Autodesk Fusion 360 part; units mm, degrees
(part 12 of 18)
  line L9010 (123.304, -201.904) -> (123.641, -202.381)
  line L9011 (33.5654, -214.426) -> (34.0223, -214.047)
  line L9012 (54.0585, -215.371) -> (54.5813, -215.09)
  line L9013 (19.0291, -207.555) -> (19.0332, -207.131)
  line L9014 (37.1268, -207.35) -> (37.1251, -207.524)
  line L9015 (29.2581, -216.323) -> (28.6766, -216.38)
  line L9016 (55.5654, -214.426) -> (56.0223, -214.047)
  line L9017 (52.4039, -216.096) -> (51.8346, -216.228)
  line L9018 (41.7774, -210.959) -> (41.5618, -210.416)
  line L9019 (50.0926, -216.4) -> (49.5085, -216.382)
  line L9020 (19.3817, -209.86) -> (19.2379, -209.293)
  line L9021 (47.1318, -215.807) -> (47.6987, -215.983)
  line L9022 (35.9457, -202.88) -> (36.2178, -203.397)
  line L9023 (36.7582, -209.547) -> (36.8847, -208.967)
  line L9024 (55.5358, -214.568) -> (55.0587, -214.905)
  line L9025 (41.0332, -207.131) -> (41.0347, -206.971)
  line L9026 (124.957, -205.608) -> (125.051, -206.184)
  line L9027 (23.2676, -199.684) -> (23.7724, -199.389)
  line L9028 (58.3321, -203.88) -> (58.084, -203.34)
  line L9029 (36.084, -203.34) -> (35.8006, -202.818)
  line L9030 (20.402, -202.554) -> (20.7274, -202.069)
  line L9031 (110.32, -200.367) -> (110.783, -200.01)
  line L9032 (19.495, -204.792) -> (19.3443, -205.366)
  line L9033 (53.9179, -199.261) -> (53.3734, -199.024)
  line L9034 (26.5208, -198.435) -> (27.0994, -198.353)
  line L9035 (50.483, -198.404) -> (49.8893, -198.397)
  line L9036 (58.7185, -205.002) -> (58.5439, -204.435)
  line L9037 (43.3513, -213.406) -> (42.9746, -212.959)
  line L9038 (21.3513, -213.406) -> (20.9746, -212.959)
  line L9039 (36.5935, -210.117) -> (36.7582, -209.547)
  line L9040 (22.539, -214.387) -> (23.0175, -214.739)
  line L9041 (21.8816, -200.753) -> (22.3203, -200.367)
  line L9042 (24.2951, -199.128) -> (24.8336, -198.901)
  line L9043 (42.7955, -202.137) -> (42.466, -202.631)
  line L9044 (23.6204, -215.227) -> (23.1214, -214.923)
  line L9045 (19.078, -206.388) -> (19.1589, -205.81)
  line L9046 (19.3803, -209.486) -> (19.541, -210.058)
  line L9047 (21.9695, -200.801) -> (21.5489, -201.22)
  line L9048 (24.5778, -215.593) -> (25.1318, -215.807)
  line L9049 (118.005, -198.508) -> (118.571, -198.651)
  line L9050 (36.9575, -205.608) -> (37.0514, -206.184)
  line L9051 (24.9847, -198.946) -> (24.4345, -199.169)
  line L9052 (47.5484, -198.759) -> (46.9847, -198.946)
  line L9053 (108.108, -203.06) -> (108.402, -202.554)
  line L9054 (41.3443, -205.366) -> (41.2321, -205.949)
  line L9055 (25.7803, -216.104) -> (25.2202, -215.937)
  line L9056 (41.9741, -211.163) -> (42.2446, -211.691)
  line L9057 (54.5607, -215.211) -> (54.0441, -215.484)
  line L9058 (29.4301, -198.402) -> (30.0047, -198.508)
  line L9059 (41.5618, -210.416) -> (41.3817, -209.86)
  line L9060 (24.8336, -198.901) -> (25.3856, -198.709)
  line L9061 (20.2446, -211.691) -> (20.5495, -212.201)
  line L9062 (20.1085, -203.06) -> (20.402, -202.554)
  line L9063 (112.295, -199.128) -> (112.834, -198.901)
  line L9064 (57.8006, -202.818) -> (57.4833, -202.317)
  line L9065 (107.277, -205.237) -> (107.432, -204.674)
  line L9066 (22.3203, -200.367) -> (22.7829, -200.01)
  line L9067 (42.466, -202.631) -> (42.17, -203.146)
  line L9068 (44.539, -214.387) -> (45.0175, -214.739)
  line L9069 (34.3423, -200.952) -> (33.9045, -200.551)
  line L9070 (35.6409, -202.381) -> (35.9457, -202.88)
  line L9071 (58.8847, -208.967) -> (58.9725, -208.379)
  line L9072 (32.1995, -199.294) -> (32.7108, -199.576)
  line L9073 (52.9627, -215.827) -> (53.5182, -215.617)
  line L9074 (20.8876, -212.689) -> (21.2572, -213.154)
  line L9075 (43.2572, -213.154) -> (43.6569, -213.593)
  line L9076 (59.1251, -207.524) -> (59.0951, -208.107)
  line L9077 (33.2028, -199.892) -> (33.6734, -200.238)
  line L9078 (124.659, -204.478) -> (124.827, -205.038)
  line L9079 (21.7561, -213.827) -> (21.3513, -213.406)
  line L9080 (33.6734, -200.238) -> (34.1207, -200.614)
  line L9081 (27.4521, -216.283) -> (28.0455, -216.305)
  line L9082 (116.85, -198.333) -> (117.43, -198.402)
  line L9083 (30.8143, -198.824) -> (30.2432, -198.661)
  line L9084 (58.5439, -204.435) -> (58.3321, -203.88)
  line L9085 (49.4521, -216.283) -> (50.0455, -216.305)
  line L9086 (35.1986, -212.934) -> (34.8234, -213.382)
  line L9087 (36.7806, -209.829) -> (36.6024, -210.386)
  line L9088 (120.199, -199.294) -> (120.711, -199.576)
  line L9089 (41.3803, -209.486) -> (41.541, -210.058)
  line L9090 (109.469, -201.166) -> (109.882, -200.753)
  line L9091 (35.1334, -201.837) -> (34.7525, -201.381)
  line L9092 (58.3914, -210.676) -> (58.5935, -210.117)
  line L9093 (19.232, -205.949) -> (19.1587, -206.538)
  line L9094 (36.3321, -203.88) -> (36.084, -203.34)
  line L9095 (51.6626, -198.537) -> (51.075, -198.451)
  line L9096 (33.5358, -214.568) -> (33.0587, -214.905)
  line L9097 (26.35, -216.234) -> (25.7803, -216.104)
  line L9098 (42.2446, -211.691) -> (42.5495, -212.201)
  line L9099 (23.5183, -215.058) -> (24.0392, -215.343)
  line L9100 (34.7525, -201.381) -> (34.3423, -200.952)
  line L9101 (19.7774, -210.959) -> (19.5618, -210.416)
  line L9102 (29.8162, -216.134) -> (30.3945, -216)
  line L9103 (30.2432, -198.661) -> (29.6626, -198.537)
  line L9104 (23.9003, -199.429) -> (23.3845, -199.723)
  line L9105 (57.1334, -201.837) -> (56.7525, -201.381)
  line L9106 (51.2581, -216.323) -> (50.6766, -216.38)
  line L9107 (53.3734, -199.024) -> (52.8143, -198.824)
  line L9108 (19.7392, -210.617) -> (19.9741, -211.163)
  line L9109 (29.2302, -216.23) -> (29.8162, -216.134)
  line L9110 (42.5495, -212.201) -> (42.8876, -212.689)
  line L9111 (58.5935, -210.117) -> (58.7582, -209.547)
  line L9112 (56.8234, -213.382) -> (56.42, -213.805)
  line L9113 (56.453, -213.638) -> (56.8557, -213.201)
  line L9114 (58.8266, -205.038) -> (58.9575, -205.608)
  line L9115 (44.643, -214.587) -> (44.1873, -214.221)
  line L9116 (56.8557, -213.201) -> (57.2286, -212.739)
  line L9117 (41.2379, -209.293) -> (41.1309, -208.719)
  line L9118 (118.571, -198.651) -> (119.128, -198.83)
  line L9119 (123.641, -202.381) -> (123.946, -202.88)
  line L9120 (114.521, -198.435) -> (115.099, -198.353)
  line L9121 (125.108, -206.766) -> (125.127, -207.35)
  line L9122 (33.9045, -200.551) -> (33.4411, -200.179)
  line L9123 (45.0175, -214.739) -> (45.5183, -215.058)
  line L9124 (23.7724, -199.389) -> (24.2951, -199.128)
  line L9125 (26.1233, -198.611) -> (25.5484, -198.759)
  line L9126 (120.711, -199.576) -> (121.203, -199.892)
  line L9127 (41.0612, -208.139) -> (41.0291, -207.555)
  line L9128 (122.543, -201.018) -> (122.938, -201.449)
  line L9129 (21.4688, -201.166) -> (21.8816, -200.753)
  line L9130 (19.2379, -209.293) -> (19.1309, -208.719)
  line L9131 (20.466, -202.631) -> (20.17, -203.146)
  line L9132 (113.949, -198.554) -> (114.521, -198.435)
  line L9133 (112.834, -198.901) -> (113.386, -198.709)
  line L9134 (19.6834, -204.229) -> (19.495, -204.792)
  line L9135 (49.2963, -198.429) -> (48.7068, -198.5)
  line L9136 (36.8266, -205.038) -> (36.9575, -205.608)
  line L9137 (49.8893, -198.397) -> (49.2963, -198.429)
  line L9138 (58.9725, -208.379) -> (59.0211, -207.787)
  line L9139 (30.9634, -215.927) -> (30.4039, -216.096)
  line L9140 (44.0847, -214.005) -> (44.539, -214.387)
  line L9141 (20.17, -203.146) -> (19.9088, -203.679)
  line L9142 (46.9847, -198.946) -> (46.4345, -199.169)
  line L9143 (58.7582, -209.547) -> (58.8847, -208.967)
  line L9144 (24.0392, -215.343) -> (24.5778, -215.593)
  line L9145 (147.021, -184.087) -> (147.032, -183.65)
  line L9146 (136.861, -192.522) -> (137.452, -192.583)
  line L9147 (131.549, -201.22) -> (131.157, -201.666)
  line L9148 (152.245, -187.991) -> (152.55, -188.501)
  line L9149 (129.777, -210.959) -> (129.562, -210.416)
  line L9150 (169.051, -182.484) -> (169.108, -183.066)
  line L9151 (131.756, -213.827) -> (131.351, -213.406)
  line L9152 (132.643, -214.587) -> (132.187, -214.221)
  line L9153 (164.044, -191.784) -> (163.511, -192.023)
  line L9154 (146.957, -181.908) -> (147.051, -182.484)
  line L9155 (141.373, -199.024) -> (140.814, -198.824)
  line L9156 (153.084, -177.906) -> (153.469, -177.466)
  line L9157 (131.157, -177.966) -> (130.795, -178.437)
  line L9158 (129.739, -210.617) -> (129.974, -211.163)
  line L9159 (138.85, -174.633) -> (139.43, -174.702)
  line L9160 (131.351, -213.406) -> (130.975, -212.959)
  line L9161 (168.389, -187.23) -> (168.14, -187.759)
  line L9162 (167.544, -188.763) -> (167.199, -189.234)
  line L9163 (146.332, -203.88) -> (146.084, -203.34)
  line L9164 (146.922, -185.562) -> (146.781, -186.129)
  line L9165 (140.963, -192.227) -> (140.404, -192.396)
  line L9166 (146.953, -206.166) -> (146.855, -205.58)
  line L9167 (164.561, -191.511) -> (164.044, -191.784)
  line L9168 (133.518, -215.058) -> (134.039, -215.343)
  line L9169 (151.238, -185.593) -> (151.131, -185.019)
  line L9170 (132.417, -176.71) -> (131.97, -177.101)
  line L9171 (164.711, -175.876) -> (165.203, -176.192)
  line L9172 (154.32, -176.667) -> (154.783, -176.31)
  line L9173 (132.32, -176.667) -> (132.783, -176.31)
  line L9174 (133.62, -215.227) -> (133.121, -214.923)
  line L9175 (130.55, -188.501) -> (130.888, -188.989)
  line L9176 (153.469, -177.466) -> (153.882, -177.053)
  line L9177 (141.511, -192.023) -> (140.963, -192.227)
  line L9178 (129.174, -184.617) -> (129.258, -185.205)
  line L9179 (168.456, -180.231) -> (168.659, -180.778)
  line L9180 (142.059, -191.671) -> (142.581, -191.39)
  line L9181 (129.035, -183.271) -> (129.078, -182.688)
  line L9182 (130.975, -212.959) -> (130.627, -212.489)
  line L9183 (129.061, -208.139) -> (129.029, -207.555)
  line L9184 (143.904, -176.851) -> (143.441, -176.479)
  line L9185 (144.938, -177.749) -> (145.304, -178.204)
  line L9186 (144.022, -190.347) -> (144.453, -189.938)
  line L9187 (142.561, -215.211) -> (142.044, -215.484)
  line L9188 (151.174, -184.617) -> (151.258, -185.205)
  line L9189 (162.571, -174.951) -> (163.128, -175.13)
  line L9190 (142.561, -191.511) -> (142.044, -191.784)
  line L9191 (131.157, -201.666) -> (130.795, -202.137)
  line L9192 (129.683, -180.529) -> (129.495, -181.092)
  line L9193 (129.739, -186.917) -> (129.974, -187.463)
  line L9194 (140.963, -192.127) -> (141.518, -191.917)
  line L9195 (142.044, -191.784) -> (141.511, -192.023)
  line L9196 (132.085, -190.305) -> (132.539, -190.687)
  line L9197 (146.544, -180.735) -> (146.332, -180.18)
  line L9198 (143.203, -176.192) -> (143.673, -176.538)
  line L9199 (133.018, -191.039) -> (133.518, -191.358)
  line L9200 (145.858, -188.27) -> (145.544, -188.763)
  line L9201 (158.927, -192.627) -> (158.35, -192.534)
  line L9202 (143.441, -200.179) -> (142.954, -199.84)
  line L9203 (136.927, -216.327) -> (136.35, -216.234)
  line L9204 (129.909, -179.979) -> (129.683, -180.529)
  line L9205 (129.541, -186.358) -> (129.739, -186.917)
  line L9206 (151.974, -187.463) -> (152.245, -187.991)
  line L9207 (153.257, -189.454) -> (153.657, -189.893)
  line L9208 (134.672, -192.035) -> (134.138, -191.798)
  line L9209 (129.159, -206.538) -> (129.124, -207.131)
  line L9210 (152.55, -188.501) -> (152.888, -188.989)
  line L9211 (137.452, -216.283) -> (138.046, -216.305)
  line L9212 (134.672, -215.735) -> (134.138, -215.498)
  line L9213 (146.719, -181.302) -> (146.544, -180.735)
  line L9214 (167.858, -188.27) -> (167.544, -188.763)
  line L9215 (130.311, -211.998) -> (130.028, -211.487)
  line L9216 (131.257, -189.454) -> (131.657, -189.893)
  line L9217 (141.128, -175.13) -> (141.671, -175.344)
  line L9218 (143.536, -214.568) -> (143.059, -214.905)
  line L9219 (144.543, -177.318) -> (144.938, -177.749)
  line L9220 (129.232, -205.949) -> (129.159, -206.538)
  line L9221 (152.975, -189.259) -> (152.627, -188.789)
  line L9222 (138.093, -192.7) -> (137.509, -192.682)
  line L9223 (145.641, -178.681) -> (145.946, -179.18)
  line L9224 (145.57, -188.553) -> (145.879, -188.046)
  line L9225 (145.483, -178.617) -> (145.133, -178.137)
  line L9226 (155.62, -191.527) -> (155.121, -191.223)
  line L9227 (141.518, -215.617) -> (142.059, -215.371)
  line L9228 (136.123, -174.911) -> (135.548, -175.059)
  line L9229 (129.541, -210.058) -> (129.739, -210.617)
  line L9230 (131.882, -177.053) -> (132.32, -176.667)
  line L9231 (151.541, -186.358) -> (151.739, -186.917)
  line L9232 (144.823, -189.682) -> (144.42, -190.105)
  line L9233 (167.946, -179.18) -> (168.218, -179.697)
  line L9234 (169.108, -183.066) -> (169.127, -183.65)
  line L9235 (134.834, -175.201) -> (135.386, -175.009)
  line L9236 (140.243, -198.661) -> (139.663, -198.537)
  line L9237 (141.918, -175.561) -> (141.373, -175.324)
  line L9238 (129.238, -185.593) -> (129.131, -185.019)
  line L9239 (146.885, -185.267) -> (146.972, -184.679)
  line L9240 (136.276, -216.122) -> (136.861, -216.222)
  line L9241 (130.108, -179.36) -> (130.402, -178.854)
  line L9242 (156.138, -191.798) -> (155.62, -191.527)
  line L9243 (139.835, -216.228) -> (139.258, -216.323)
  line L9244 (146.14, -187.759) -> (145.858, -188.27)
  line L9245 (140.395, -216) -> (140.963, -215.827)
  line L9246 (167.199, -189.234) -> (166.823, -189.682)
  line L9247 (155.018, -191.039) -> (155.518, -191.358)
  line L9248 (133.018, -214.739) -> (133.518, -215.058)
  line L9249 (129.13, -207.725) -> (129.174, -208.317)
  line L9250 (151.029, -183.855) -> (151.033, -183.431)
  line L9251 (153.657, -189.893) -> (154.085, -190.305)
  line L9252 (167.304, -178.204) -> (167.641, -178.681)
  line L9253 (146.972, -184.679) -> (147.021, -184.087)
  line L9254 (131.351, -189.706) -> (130.975, -189.259)
  line L9255 (151.131, -185.019) -> (151.061, -184.439)
  line L9256 (154.783, -176.31) -> (155.268, -175.984)
  line L9257 (140.963, -215.827) -> (141.518, -215.617)
  line L9258 (135.548, -198.759) -> (134.985, -198.946)
  line L9259 (147.027, -184.988) -> (146.922, -185.562)
  line L9260 (132.187, -214.221) -> (131.756, -213.827)
  line L9261 (168.218, -179.697) -> (168.456, -180.231)
  line L9262 (146.332, -180.18) -> (146.084, -179.64)
  line L9263 (143.059, -191.205) -> (142.561, -191.511)
  line L9264 (145.229, -212.739) -> (145.57, -212.253)
  line L9265 (130.975, -189.259) -> (130.627, -188.789)
  line L9266 (129.159, -182.838) -> (129.124, -183.431)
  line L9267 (141.373, -175.324) -> (140.814, -175.124)
  line L9268 (140.814, -198.824) -> (140.243, -198.661)
  line L9269 (162.963, -192.227) -> (162.404, -192.396)
  line L9270 (143.904, -200.551) -> (143.441, -200.179)
  line L9271 (130.245, -187.991) -> (130.55, -188.501)
  line L9272 (155.121, -191.223) -> (154.643, -190.887)
  line L9273 (165.059, -191.205) -> (164.561, -191.511)
  line L9274 (133.9, -199.429) -> (133.385, -199.723)
  line L9275 (137.889, -198.397) -> (137.296, -198.429)
  line L9276 (168.602, -186.686) -> (168.389, -187.23)
  line L9277 (135.548, -175.059) -> (134.985, -175.246)
  line L9278 (154.085, -190.305) -> (154.539, -190.687)
  line L9279 (133.121, -191.223) -> (132.643, -190.887)
  line L9280 (141.511, -215.723) -> (140.963, -215.927)
  line L9281 (134.985, -175.246) -> (134.434, -175.469)
  line L9282 (136.927, -192.627) -> (136.35, -192.534)
  line L9283 (157.78, -192.404) -> (157.22, -192.237)
  line L9284 (157.22, -192.237) -> (156.672, -192.035)
  line L9285 (161.43, -174.702) -> (162.005, -174.808)
  line L9286 (151.033, -183.431) -> (151.035, -183.271)
  line L9287 (153.882, -177.053) -> (154.32, -176.667)
  line L9288 (137.682, -174.609) -> (138.266, -174.602)
  line L9289 (136.707, -198.5) -> (136.123, -198.611)
  line L9290 (144.856, -213.201) -> (145.229, -212.739)
  line L9291 (146.391, -210.676) -> (146.594, -210.117)
  line L9292 (130.627, -212.489) -> (130.311, -211.998)
  line L9293 (133.772, -175.689) -> (134.295, -175.428)
  line L9294 (145.304, -178.204) -> (145.641, -178.681)
  line L9295 (151.622, -180.422) -> (151.848, -179.883)
  line L9296 (133.62, -191.527) -> (133.121, -191.223)
  line L9297 (166.543, -177.318) -> (166.938, -177.749)
  line L9298 (135.22, -192.237) -> (134.672, -192.035)
  line L9299 (136.707, -174.8) -> (136.123, -174.911)
  line L9300 (152.028, -187.787) -> (151.777, -187.259)
  line L9301 (138.266, -174.602) -> (138.85, -174.633)
  line L9302 (129.174, -208.317) -> (129.258, -208.905)
  line L9303 (145.133, -178.137) -> (144.753, -177.681)
  line L9304 (134.138, -215.498) -> (133.62, -215.227)
  line L9305 (129.495, -204.792) -> (129.344, -205.366)
  line L9306 (151.432, -180.974) -> (151.622, -180.422)
  line L9307 (155.518, -191.358) -> (156.039, -191.643)
  line L9308 (147.127, -183.65) -> (147.125, -183.824)
  line L9309 (130.627, -188.789) -> (130.311, -188.298)
  line L9310 (135.949, -174.854) -> (136.521, -174.735)
  line L9311 (154.187, -190.521) -> (153.756, -190.127)
  line L9312 (137.509, -216.382) -> (136.927, -216.327)
  line L9313 (146.781, -186.129) -> (146.602, -186.686)
  line L9314 (143.084, -191.074) -> (143.565, -190.726)
  line L9315 (134.434, -175.469) -> (133.9, -175.729)
  line L9316 (146.855, -205.58) -> (146.719, -205.002)
  line L9317 (130.795, -202.137) -> (130.466, -202.631)
  line L9318 (140.404, -216.096) -> (139.835, -216.228)
  line L9319 (140.395, -192.3) -> (140.963, -192.127)
  line L9320 (138.046, -192.605) -> (138.639, -192.587)
  line L9321 (169.027, -184.988) -> (168.922, -185.562)
  line L9322 (139.23, -216.23) -> (139.816, -216.134)
  line L9323 (166.42, -190.105) -> (165.99, -190.501)
  line L9324 (151.562, -186.716) -> (151.382, -186.16)
  line L9325 (152.402, -178.854) -> (152.727, -178.369)
  line L9326 (141.671, -175.344) -> (142.199, -175.594)
  line L9327 (160.093, -192.7) -> (159.509, -192.682)
  line L9328 (168.14, -187.759) -> (167.858, -188.27)
  line L9329 (129.131, -185.019) -> (129.061, -184.439)
  line L9330 (153.756, -190.127) -> (153.351, -189.706)
  line L9331 (166.121, -176.914) -> (166.543, -177.318)
  line L9332 (144.342, -200.952) -> (143.904, -200.551)
  line L9333 (156.672, -192.035) -> (156.138, -191.798)
  line L9334 (129.131, -208.719) -> (129.061, -208.139)
  line L9335 (144.753, -201.381) -> (144.342, -200.952)
  line L9336 (136.35, -192.534) -> (135.78, -192.404)
  line L9337 (163.128, -175.13) -> (163.671, -175.344)
  line L9338 (160.266, -174.602) -> (160.85, -174.633)
  line L9339 (140.005, -174.808) -> (140.571, -174.951)
  line L9340 (159.099, -174.653) -> (159.682, -174.609)
  line L9341 (151.035, -183.271) -> (151.078, -182.688)
  line L9342 (145.483, -202.317) -> (145.133, -201.837)
  line L9343 (147.032, -183.65) -> (147.012, -183.057)
  line L9344 (147.012, -183.057) -> (146.953, -182.466)
  line L9345 (161.258, -192.623) -> (160.677, -192.68)
  line L9346 (131.657, -189.893) -> (132.085, -190.305)
  line L9347 (145.801, -179.118) -> (145.483, -178.617)
  line L9348 (146.659, -180.778) -> (146.827, -181.338)
  line L9349 (138.483, -174.704) -> (137.889, -174.697)
  line L9350 (136.35, -216.234) -> (135.78, -216.104)
  line L9351 (138.639, -216.287) -> (139.23, -216.23)
  line L9352 (139.663, -174.837) -> (139.075, -174.751)
  line L9353 (155.268, -175.984) -> (155.772, -175.689)
  line L9354 (137.889, -174.697) -> (137.296, -174.729)
  line L9355 (139.835, -192.528) -> (139.258, -192.623)
  line L9356 (145.879, -188.046) -> (146.153, -187.519)
  line L9357 (145.544, -188.763) -> (145.199, -189.234)
  line L9358 (132.085, -214.005) -> (132.539, -214.387)
  line L9359 (131.257, -213.154) -> (131.657, -213.593)
  line L9360 (129.029, -207.555) -> (129.033, -207.131)
  line L9361 (168.781, -186.129) -> (168.602, -186.686)
  line L9362 (134.578, -215.593) -> (135.132, -215.807)
  line L9363 (129.974, -211.163) -> (130.245, -211.691)
  line L9364 (154.539, -190.687) -> (155.018, -191.039)
  line L9365 (131.97, -177.101) -> (131.549, -177.52)
  line L9366 (145.879, -211.746) -> (146.153, -211.219)
  line L9367 (140.243, -174.961) -> (139.663, -174.837)
  line L9368 (145.133, -201.837) -> (144.753, -201.381)
  line L9369 (138.677, -192.68) -> (138.093, -192.7)
  line L9370 (157.386, -175.009) -> (157.949, -174.854)
  line L9371 (146.389, -187.23) -> (146.14, -187.759)
  line L9372 (145.199, -189.234) -> (144.823, -189.682)
  line L9373 (156.295, -175.428) -> (156.834, -175.201)
  line L9374 (135.132, -192.107) -> (135.699, -192.283)
  line L9375 (129.562, -186.716) -> (129.382, -186.16)
  line L9376 (132.889, -200.051) -> (132.417, -200.41)
  line L9377 (159.509, -192.682) -> (158.927, -192.627)
  line L9378 (134.039, -191.643) -> (134.578, -191.893)
  line L9379 (142.581, -191.39) -> (143.084, -191.074)
  line L9380 (132.643, -190.887) -> (132.187, -190.521)
  line L9381 (132.539, -214.387) -> (133.018, -214.739)
  line L9382 (133.9, -175.729) -> (133.385, -176.023)
  line L9383 (129.562, -210.416) -> (129.382, -209.86)
  line L9384 (146.953, -182.466) -> (146.855, -181.88)
  line L9385 (144.753, -177.681) -> (144.342, -177.252)
  line L9386 (157.949, -174.854) -> (158.521, -174.735)
  line L9387 (133.518, -191.358) -> (134.039, -191.643)
  line L9388 (159.682, -174.609) -> (160.266, -174.602)
  line L9389 (140.571, -174.951) -> (141.128, -175.13)
  line L9390 (129.232, -182.249) -> (129.159, -182.838)
  line L9391 (165.536, -190.868) -> (165.059, -191.205)
  line L9392 (129.38, -185.786) -> (129.541, -186.358)
  line L9393 (146.885, -208.967) -> (146.972, -208.379)
  line L9394 (152.108, -179.36) -> (152.402, -178.854)
  line L9395 (145.801, -202.818) -> (145.483, -202.317)
  line L9396 (143.565, -190.726) -> (144.022, -190.347)
  line L9397 (146.827, -181.338) -> (146.957, -181.908)
  line L9398 (146.594, -210.117) -> (146.758, -209.547)
  line L9399 (131.469, -177.466) -> (131.882, -177.053)
  line L9400 (147.051, -182.484) -> (147.108, -183.066)
  line L9401 (135.699, -215.983) -> (136.276, -216.122)
  line L9402 (129.38, -209.486) -> (129.541, -210.058)
  line L9403 (130.402, -178.854) -> (130.727, -178.369)
  line L9404 (129.13, -184.025) -> (129.174, -184.617)
  line L9405 (143.441, -176.479) -> (142.954, -176.14)
  line L9406 (162.404, -192.396) -> (161.835, -192.528)
  line L9407 (137.099, -174.653) -> (137.682, -174.609)
  line L9408 (129.382, -186.16) -> (129.238, -185.593)
  line L9409 (135.386, -175.009) -> (135.949, -174.854)
  line L9410 (167.641, -178.681) -> (167.946, -179.18)
  line L9411 (169.127, -183.65) -> (169.125, -183.824)
  line L9412 (145.57, -212.253) -> (145.879, -211.746)
  line L9413 (135.132, -215.807) -> (135.699, -215.983)
  line L9414 (129.258, -185.205) -> (129.38, -185.786)
  line L9415 (147.108, -183.066) -> (147.127, -183.65)
  line L9416 (131.657, -213.593) -> (132.085, -214.005)
  line L9417 (130.55, -212.201) -> (130.888, -212.689)
  line L9418 (139.43, -174.702) -> (140.005, -174.808)
  line L9419 (137.296, -198.429) -> (136.707, -198.5)
  line L9420 (168.957, -181.908) -> (169.051, -182.484)
  line L9421 (133.121, -214.923) -> (132.643, -214.587)
  line L9422 (132.187, -190.521) -> (131.756, -190.127)
  line L9423 (154.643, -190.887) -> (154.187, -190.521)
  line L9424 (144.42, -190.105) -> (143.99, -190.501)
  line L9425 (140.814, -175.124) -> (140.243, -174.961)
  line L9426 (168.659, -180.778) -> (168.827, -181.338)
  line L9427 (139.23, -192.53) -> (139.816, -192.434)
  line L9428 (129.124, -207.131) -> (129.13, -207.725)
  line L9429 (151.078, -182.688) -> (151.159, -182.11)
  line L9430 (142.711, -175.876) -> (143.203, -176.192)
  line L9431 (143.99, -190.501) -> (143.536, -190.868)
  line L9432 (130.17, -179.446) -> (129.909, -179.979)
  line L9433 (130.466, -202.631) -> (130.17, -203.146)
  line L9434 (129.035, -206.971) -> (129.078, -206.388)
  line L9435 (164.199, -175.594) -> (164.711, -175.876)
  line L9436 (151.159, -182.11) -> (151.277, -181.537)
  line L9437 (142.446, -175.833) -> (141.918, -175.561)
  line L9438 (129.974, -187.463) -> (130.245, -187.991)
  line L9439 (129.061, -184.439) -> (129.029, -183.855)
  line L9440 (146.391, -186.976) -> (146.594, -186.417)
  line L9441 (158.521, -174.735) -> (159.099, -174.653)
  line L9442 (129.909, -203.679) -> (129.683, -204.229)
  line L9443 (146.855, -181.88) -> (146.719, -181.302)
  line L9444 (146.153, -211.219) -> (146.391, -210.676)
  line L9445 (140.963, -215.927) -> (140.404, -216.096)
  line L9446 (142.044, -215.484) -> (141.511, -215.723)
  line L9447 (129.777, -187.259) -> (129.562, -186.716)
  line L9448 (130.795, -178.437) -> (130.466, -178.931)
  line L9449 (147.012, -206.757) -> (146.953, -206.166)
  line L9450 (146.602, -186.686) -> (146.389, -187.23)
  line L9451 (146.153, -187.519) -> (146.391, -186.976)
  line L9452 (166.938, -177.749) -> (167.304, -178.204)
  line L9453 (160.677, -192.68) -> (160.093, -192.7)
  line L9454 (141.918, -199.261) -> (141.373, -199.024)
  line L9455 (132.889, -176.351) -> (132.417, -176.71)
  line L9456 (129.495, -181.092) -> (129.344, -181.666)
  line L9457 (130.727, -178.369) -> (131.084, -177.906)
  line L9458 (136.861, -216.222) -> (137.452, -216.283)
  line L9459 (133.268, -175.984) -> (133.772, -175.689)
  line L9460 (163.671, -175.344) -> (164.199, -175.594)
  line L9461 (146.456, -180.231) -> (146.659, -180.778)
  line L9462 (142.581, -215.09) -> (143.084, -214.774)
  line L9463 (152.888, -188.989) -> (153.257, -189.454)
  line L9464 (129.432, -180.974) -> (129.622, -180.422)
  line L9465 (129.029, -183.855) -> (129.033, -183.431)
  line L9466 (163.511, -192.023) -> (162.963, -192.227)
  line L9467 (144.453, -213.638) -> (144.856, -213.201)
  line L9468 (146.972, -208.379) -> (147.021, -207.787)
  line L9469 (147.021, -207.787) -> (147.032, -207.35)
  line L9470 (133.385, -176.023) -> (132.889, -176.351)
  line L9471 (151.38, -185.786) -> (151.541, -186.358)
  line L9472 (168.827, -181.338) -> (168.957, -181.908)
  line L9473 (168.922, -185.562) -> (168.781, -186.129)
  line L9474 (133.385, -199.723) -> (132.889, -200.051)
  line L9475 (165.203, -176.192) -> (165.673, -176.538)
  line L9476 (132.539, -190.687) -> (133.018, -191.039)
  line L9477 (139.075, -198.451) -> (138.483, -198.404)
  line L9478 (143.084, -214.774) -> (143.565, -214.426)
  line L9479 (138.093, -216.4) -> (137.509, -216.382)
  line L9480 (169.125, -183.824) -> (169.095, -184.407)
  line L9481 (156.834, -175.201) -> (157.386, -175.009)
  line L9482 (155.772, -175.689) -> (156.295, -175.428)
  line L9483 (144.453, -189.938) -> (144.856, -189.501)
  line L9484 (147.125, -183.824) -> (147.095, -184.407)
  line L9485 (134.985, -198.946) -> (134.434, -199.169)
  line L9486 (151.739, -186.917) -> (151.974, -187.463)
  line L9487 (138.639, -192.587) -> (139.23, -192.53)
  line L9488 (151.777, -187.259) -> (151.562, -186.716)
  line L9489 (147.032, -207.35) -> (147.012, -206.757)
  line L9490 (137.296, -174.729) -> (136.707, -174.8)
  line L9491 (137.452, -192.583) -> (138.046, -192.605)
  line L9492 (147.095, -184.407) -> (147.027, -184.988)
  line L9493 (129.382, -209.86) -> (129.238, -209.293)
  line L9494 (132.783, -176.31) -> (133.268, -175.984)
  line L9495 (162.005, -174.808) -> (162.571, -174.951)
  line L9496 (140.404, -192.396) -> (139.835, -192.528)
  line L9497 (136.123, -198.611) -> (135.548, -198.759)
  line L9498 (151.848, -179.883) -> (152.108, -179.36)
  line L9499 (134.295, -175.428) -> (134.834, -175.201)
  line L9500 (142.059, -215.371) -> (142.581, -215.09)
  line L9501 (130.888, -212.689) -> (131.257, -213.154)
  line L9502 (146.544, -204.435) -> (146.332, -203.88)
  line L9503 (146.758, -185.847) -> (146.885, -185.267)
  line L9504 (153.351, -189.706) -> (152.975, -189.259)
  line L9505 (129.124, -183.431) -> (129.13, -184.025)
  line L9506 (145.229, -189.039) -> (145.57, -188.553)
  line L9507 (130.466, -178.931) -> (130.17, -179.446)
  line L9508 (143.536, -190.868) -> (143.059, -191.205)
  line L9509 (144.342, -177.252) -> (143.904, -176.851)
  line L9510 (142.446, -199.533) -> (141.918, -199.261)
  line L9511 (146.218, -179.697) -> (146.456, -180.231)
  line L9512 (139.258, -192.623) -> (138.677, -192.68)
  line L9513 (134.434, -199.169) -> (133.9, -199.429)
  line L9514 (131.756, -190.127) -> (131.351, -189.706)
  line L9515 (146.719, -205.002) -> (146.544, -204.435)
  line L9516 (129.344, -181.666) -> (129.232, -182.249)
  line L9517 (135.78, -216.104) -> (135.22, -215.937)
  line L9518 (134.138, -191.798) -> (133.62, -191.527)
  line L9519 (166.823, -189.682) -> (166.42, -190.105)
  line L9520 (129.159, -182.11) -> (129.277, -181.537)
  line L9521 (129.622, -180.422) -> (129.848, -179.883)
  line L9522 (152.311, -188.298) -> (152.028, -187.787)
  line L9523 (130.028, -211.487) -> (129.777, -210.959)
  line L9524 (129.344, -205.366) -> (129.232, -205.949)
  line L9525 (151.258, -185.205) -> (151.38, -185.786)
  line L9526 (129.277, -181.537) -> (129.432, -180.974)
  line L9527 (145.946, -179.18) -> (146.218, -179.697)
  line L9528 (151.061, -184.439) -> (151.029, -183.855)
  line L9529 (151.277, -181.537) -> (151.432, -180.974)
  line L9530 (138.483, -198.404) -> (137.889, -198.397)
  line L9531 (139.816, -216.134) -> (140.395, -216)
  line L9532 (131.97, -200.801) -> (131.549, -201.22)
  line L9533 (129.848, -179.883) -> (130.108, -179.36)
  line L9534 (142.199, -175.594) -> (142.711, -175.876)
  line L9535 (130.888, -188.989) -> (131.257, -189.454)
  line L9536 (130.311, -188.298) -> (130.028, -187.787)
  line L9537 (134.578, -191.893) -> (135.132, -192.107)
  line L9538 (144.856, -189.501) -> (145.229, -189.039)
  line L9539 (146.084, -203.34) -> (145.801, -202.818)
  line L9540 (139.075, -174.751) -> (138.483, -174.704)
  line L9541 (129.238, -209.293) -> (129.131, -208.719)
  line L9542 (134.039, -215.343) -> (134.578, -215.593)
  line L9543 (138.677, -216.38) -> (138.093, -216.4)
  line L9544 (131.549, -177.52) -> (131.157, -177.966)
  line L9545 (129.033, -207.131) -> (129.035, -206.971)
  line L9546 (136.521, -174.735) -> (137.099, -174.653)
  line L9547 (143.565, -214.426) -> (144.022, -214.047)
  line L9548 (165.673, -176.538) -> (166.121, -176.914)
  line L9549 (152.627, -188.789) -> (152.311, -188.298)
  line L9550 (142.954, -176.14) -> (142.446, -175.833)
  line L9551 (130.028, -187.787) -> (129.777, -187.259)
  line L9552 (143.673, -176.538) -> (144.121, -176.914)
  line L9553 (141.518, -191.917) -> (142.059, -191.671)
  line L9554 (138.046, -216.305) -> (138.639, -216.287)
  line L9555 (143.059, -214.905) -> (142.561, -215.211)
  line L9556 (165.99, -190.501) -> (165.536, -190.868)
  line L9557 (160.85, -174.633) -> (161.43, -174.702)
  line L9558 (144.121, -176.914) -> (144.543, -177.318)
  line L9559 (139.663, -198.537) -> (139.075, -198.451)
  line L9560 (136.276, -192.422) -> (136.861, -192.522)
  line L9561 (146.084, -179.64) -> (145.801, -179.118)
  line L9562 (129.078, -182.688) -> (129.159, -182.11)
  line L9563 (161.835, -192.528) -> (161.258, -192.623)
  line L9564 (130.17, -203.146) -> (129.909, -203.679)
  line L9565 (139.816, -192.434) -> (140.395, -192.3)
  line L9566 (131.084, -177.906) -> (131.469, -177.466)
  line L9567 (144.022, -214.047) -> (144.453, -213.638)
  line L9568 (130.245, -211.691) -> (130.55, -212.201)
  line L9569 (158.35, -192.534) -> (157.78, -192.404)
  line L9570 (135.22, -215.937) -> (134.672, -215.735)
  line L9571 (169.095, -184.407) -> (169.027, -184.988)
  line L9572 (151.382, -186.16) -> (151.238, -185.593)
  line L9573 (152.727, -178.369) -> (153.084, -177.906)
  line L9574 (129.258, -208.905) -> (129.38, -209.486)
  line L9575 (129.683, -204.229) -> (129.495, -204.792)
  line L9576 (146.758, -209.547) -> (146.885, -208.967)
  line L9577 (139.258, -216.323) -> (138.677, -216.38)
  line L9578 (146.594, -186.417) -> (146.758, -185.847)
  line L9579 (132.417, -200.41) -> (131.97, -200.801)
  line L9580 (135.699, -192.283) -> (136.276, -192.422)
  line L9581 (135.78, -192.404) -> (135.22, -192.237)
  line L9582 (129.033, -183.431) -> (129.035, -183.271)
  line L9583 (142.954, -199.84) -> (142.446, -199.533)
  line L9584 (137.509, -192.682) -> (136.927, -192.627)
  line L9585 (74.2432, -198.661) -> (73.6626, -198.537)
  line L9586 (146.218, -203.397) -> (146.456, -203.931)
  line L9587 (175.882, -153.353) -> (176.32, -152.967)
  line L9588 (184.005, -151.108) -> (184.571, -151.251)
  line L9589 (77.9903, -214.201) -> (77.5358, -214.568)
  line L9590 (63.6834, -204.229) -> (63.495, -204.792)
  line L9591 (76.1995, -199.294) -> (76.7108, -199.576)
  line L9592 (141.128, -198.83) -> (141.671, -199.044)
  line L9593 (74.9634, -215.927) -> (74.4039, -216.096)
  line L9594 (80.9531, -206.166) -> (80.8551, -205.58)
  line L9595 (64.7274, -202.069) -> (65.0836, -201.606)
  line L9596 (71.0994, -198.353) -> (71.682, -198.309)
  line L9597 (78.5428, -201.018) -> (78.9379, -201.449)
  line L9598 (67.3845, -199.723) -> (66.8893, -200.051)
  line L9599 (78.7525, -201.381) -> (78.3423, -200.952)
  line L9600 (178.138, -168.098) -> (177.62, -167.827)
  line L9601 (146.659, -204.478) -> (146.827, -205.038)
  line L9602 (72.0926, -216.4) -> (71.5085, -216.382)
  line L9603 (147.127, -207.35) -> (147.125, -207.524)
  line L9604 (173.029, -160.155) -> (173.033, -159.731)
  line L9605 (80.9224, -209.262) -> (80.7806, -209.829)
  line L9606 (177.121, -167.523) -> (176.643, -167.187)
  line L9607 (176.187, -166.821) -> (175.756, -166.427)
  line L9608 (80.1404, -211.459) -> (79.8585, -211.97)
  line L9609 (173.848, -156.183) -> (174.108, -155.66)
  line L9610 (79.8585, -211.97) -> (79.5441, -212.463)
  line L9611 (187.536, -167.168) -> (187.059, -167.505)
  line L9612 (85.2321, -158.549) -> (85.1587, -159.138)
  line L9613 (183.835, -168.828) -> (183.258, -168.923)
  line L9614 (173.258, -161.505) -> (173.38, -162.086)
  line L9615 (189.946, -155.48) -> (190.218, -155.997)
  line L9616 (173.159, -158.41) -> (173.277, -157.837)
  line L9617 (177.772, -151.989) -> (178.295, -151.728)
  line L9618 (173.033, -159.731) -> (173.035, -159.571)
  line L9619 (64.5495, -212.201) -> (64.8876, -212.689)
  line L9620 (144.121, -200.614) -> (144.543, -201.018)
  line L9621 (80.4559, -203.931) -> (80.6591, -204.478)
  line L9622 (85.495, -157.392) -> (85.3443, -157.966)
  line L9623 (80.5439, -204.435) -> (80.3321, -203.88)
  line L9624 (139.43, -198.402) -> (140.005, -198.508)
  line L9625 (145.858, -211.97) -> (145.544, -212.463)
  line L9626 (146.957, -205.608) -> (147.051, -206.184)
  line L9627 (77.9045, -200.551) -> (77.4411, -200.179)
  line L9628 (71.2963, -198.429) -> (70.7068, -198.5)
  line L9629 (190.456, -156.531) -> (190.659, -157.078)
  line L9630 (188.42, -166.405) -> (187.99, -166.801)
  line L9631 (66.539, -214.387) -> (67.0175, -214.739)
  line L9632 (77.0587, -214.905) -> (76.5607, -215.211)
  line L9633 (92.1233, -151.211) -> (91.5484, -151.359)
  line L9634 (80.8266, -205.038) -> (80.9575, -205.608)
  line L9635 (79.2286, -212.739) -> (79.57, -212.253)
  line L9636 (80.3887, -210.93) -> (80.1404, -211.459)
  line L9637 (133.268, -199.684) -> (133.772, -199.389)
  line L9638 (73.8346, -216.228) -> (73.2581, -216.323)
  line L9639 (63.2769, -205.237) -> (63.4315, -204.674)
  line L9640 (145.304, -201.904) -> (145.641, -202.381)
  line L9641 (176.32, -152.967) -> (176.783, -152.61)
  line L9642 (71.682, -198.309) -> (72.2663, -198.302)
  line L9643 (87.157, -154.266) -> (86.7955, -154.737)
  line L9644 (191.125, -160.124) -> (191.095, -160.707)
  line L9645 (63.0332, -207.131) -> (63.0347, -206.971)
  line L9646 (182.677, -168.98) -> (182.093, -169)
  line L9647 (73.075, -198.451) -> (72.483, -198.404)
  line L9648 (89.9003, -152.029) -> (89.3845, -152.323)
  line L9649 (68.5778, -215.593) -> (69.1318, -215.807)
  line L9650 (80.6024, -210.386) -> (80.3887, -210.93)
  line L9651 (180.521, -151.035) -> (181.099, -150.953)
  line L9652 (67.9003, -199.429) -> (67.3845, -199.723)
  line L9653 (79.5441, -212.463) -> (79.1986, -212.934)
  line L9654 (64.6274, -212.489) -> (64.3113, -211.998)
  line L9655 (73.6626, -198.537) -> (73.075, -198.451)
  line L9656 (63.1587, -206.538) -> (63.1245, -207.131)
  line L9657 (64.402, -202.554) -> (64.7274, -202.069)
  line L9658 (175.756, -166.427) -> (175.351, -166.006)
  line L9659 (81.0318, -207.35) -> (81.0121, -206.757)
  line L9660 (63.3443, -205.366) -> (63.232, -205.949)
  line L9661 (130.108, -203.06) -> (130.402, -202.554)
  line L9662 (144.543, -201.018) -> (144.938, -201.449)
  line L9663 (66.3203, -200.367) -> (66.7829, -200.01)
  line L9664 (138.85, -198.333) -> (139.43, -198.402)
  line L9665 (67.2676, -199.684) -> (67.7724, -199.389)
  line L9666 (81.0274, -208.688) -> (80.9224, -209.262)
  line L9667 (85.1245, -159.731) -> (85.1297, -160.325)
  line L9668 (147.108, -206.766) -> (147.127, -207.35)
  line L9669 (173.38, -162.086) -> (173.541, -162.658)
  line L9670 (77.5358, -214.568) -> (77.0587, -214.905)
  line L9671 (185.671, -151.644) -> (186.199, -151.894)
  line L9672 (134.834, -198.901) -> (135.386, -198.709)
  line L9673 (65.5489, -201.22) -> (65.157, -201.666)
  line L9674 (72.6766, -216.38) -> (72.0926, -216.4)
  line L9675 (70.7068, -198.5) -> (70.1233, -198.611)
  line L9676 (173.238, -161.893) -> (173.131, -161.319)
  line L9677 (129.159, -205.81) -> (129.277, -205.237)
  line L9678 (136.521, -198.435) -> (137.099, -198.353)
  line L9679 (80.8847, -208.967) -> (80.9725, -208.379)
  line L9680 (75.5109, -215.723) -> (74.9634, -215.927)
  line L9681 (64.7955, -202.137) -> (64.466, -202.631)
  line L9682 (64.0276, -211.487) -> (63.7774, -210.959)
  line L9683 (74.0047, -198.508) -> (74.5713, -198.651)
  line L9684 (66.643, -214.587) -> (66.1873, -214.221)
  line L9685 (86.466, -155.231) -> (86.17, -155.746)
  line L9686 (130.402, -202.554) -> (130.727, -202.069)
  line L9687 (63.3817, -209.86) -> (63.2379, -209.293)
  line L9688 (138.266, -198.302) -> (138.85, -198.333)
  line L9689 (72.483, -198.404) -> (71.8893, -198.397)
  line L9690 (91.5484, -151.359) -> (90.9847, -151.546)
  line L9691 (141.671, -199.044) -> (142.199, -199.294)
  line L9692 (80.9725, -208.379) -> (81.0211, -207.787)
  line L9693 (188.938, -154.049) -> (189.304, -154.504)
  line L9694 (189.544, -165.063) -> (189.199, -165.534)
  line L9695 (63.1309, -208.719) -> (63.0612, -208.139)
  line L9696 (177.62, -167.827) -> (177.121, -167.523)
  line L9697 (187.059, -167.505) -> (186.561, -167.811)
  line L9698 (146.456, -203.931) -> (146.659, -204.478)
  line L9699 (89.3845, -152.323) -> (88.8893, -152.651)
  line L9700 (72.2663, -198.302) -> (72.8498, -198.333)
  line L9701 (173.078, -158.988) -> (173.159, -158.41)
  line L9702 (79.8785, -211.746) -> (80.1527, -211.219)
  line L9703 (145.946, -202.88) -> (146.218, -203.397)
  line L9704 (70.8615, -216.222) -> (71.4521, -216.283)
  line L9705 (146.14, -211.459) -> (145.858, -211.97)
  line L9706 (81.1079, -206.766) -> (81.1268, -207.35)
  line L9707 (144.42, -213.805) -> (143.99, -214.201)
  line L9708 (63.232, -205.949) -> (63.1587, -206.538)
  line L9709 (74.9627, -215.827) -> (75.5182, -215.617)
  line L9710 (63.8482, -203.583) -> (64.1085, -203.06)
  line L9711 (190.957, -158.208) -> (191.051, -158.784)
  line L9712 (80.8551, -205.58) -> (80.7185, -205.002)
  line L9713 (191.108, -159.366) -> (191.127, -159.95)
  line L9714 (69.3856, -198.709) -> (69.9488, -198.554)
  line L9715 (130.727, -202.069) -> (131.084, -201.606)
  line L9716 (131.882, -200.753) -> (132.32, -200.367)
  line L9717 (180.35, -168.834) -> (179.78, -168.704)
  line L9718 (140.005, -198.508) -> (140.571, -198.651)
  line L9719 (75.9179, -199.261) -> (75.3734, -199.024)
  line L9720 (70.5208, -198.435) -> (71.0994, -198.353)
  line L9721 (181.682, -150.909) -> (182.266, -150.902)
  line L9722 (77.2028, -199.892) -> (77.6734, -200.238)
  line L9723 (190.659, -157.078) -> (190.827, -157.638)
  line L9724 (174.727, -154.669) -> (175.084, -154.206)
  line L9725 (146.781, -209.829) -> (146.602, -210.386)
  line L9726 (81.1251, -207.524) -> (81.0951, -208.107)
  line L9727 (76.7108, -199.576) -> (77.2028, -199.892)
  line L9728 (146.602, -210.386) -> (146.389, -210.93)
  line L9729 (85.6834, -156.829) -> (85.495, -157.392)
  line L9730 (182.093, -169) -> (181.509, -168.982)
  line L9731 (69.7803, -216.104) -> (69.2202, -215.937)
  line L9732 (191.095, -160.707) -> (191.027, -161.288)
  line L9733 (179.22, -168.537) -> (178.672, -168.335)
  line L9734 (65.3513, -213.406) -> (64.9746, -212.959)
  line L9735 (65.7561, -213.827) -> (65.3513, -213.406)
  line L9736 (190.389, -163.53) -> (190.14, -164.059)
  line L9737 (64.466, -202.631) -> (64.17, -203.146)
  line L9738 (63.9088, -203.679) -> (63.6834, -204.229)
  line L9739 (65.157, -201.666) -> (64.7955, -202.137)
  line L9740 (64.17, -203.146) -> (63.9088, -203.679)
  line L9741 (173.777, -163.559) -> (173.562, -163.016)
  line L9742 (64.9746, -212.959) -> (64.6274, -212.489)
  line L9743 (188.823, -165.982) -> (188.42, -166.405)
  line L9744 (80.7582, -209.547) -> (80.8847, -208.967)
  line L9745 (77.6734, -200.238) -> (78.1207, -200.614)
  line L9746 (175.469, -153.766) -> (175.882, -153.353)
  line L9747 (176.783, -152.61) -> (177.268, -152.284)
  line L9748 (75.1275, -198.83) -> (75.671, -199.044)
  line L9749 (78.453, -213.638) -> (78.8557, -213.201)
  line L9750 (73.4301, -198.402) -> (74.0047, -198.508)
  line L9751 (86.7955, -154.737) -> (86.466, -155.231)
  line L9752 (174.311, -164.598) -> (174.028, -164.087)
  line L9753 (190.14, -164.059) -> (189.858, -164.57)
  line L9754 (90.4345, -151.769) -> (89.9003, -152.029)
  line L9755 (77.0844, -214.774) -> (77.5654, -214.426)
  line L9756 (65.2572, -213.154) -> (65.6569, -213.593)
  line L9757 (78.3423, -200.952) -> (77.9045, -200.551)
  line L9758 (79.3045, -201.904) -> (79.6409, -202.381)
  line L9759 (188.121, -153.214) -> (188.543, -153.618)
  line L9760 (181.509, -168.982) -> (180.927, -168.927)
  line L9761 (63.0347, -206.971) -> (63.078, -206.388)
  line L9762 (174.028, -164.087) -> (173.777, -163.559)
  line L9763 (173.622, -156.722) -> (173.848, -156.183)
  line L9764 (146.922, -209.262) -> (146.781, -209.829)
  line L9765 (142.199, -199.294) -> (142.711, -199.576)
  line L9766 (73.8162, -216.134) -> (74.3945, -216)
  line L9767 (187.673, -152.838) -> (188.121, -153.214)
  line L9768 (185.128, -151.43) -> (185.671, -151.644)
  line L9769 (75.5182, -215.617) -> (76.0585, -215.371)
  line L9770 (185.511, -168.323) -> (184.963, -168.527)
  line L9771 (70.1233, -198.611) -> (69.5484, -198.759)
  line L9772 (85.1297, -160.325) -> (85.1742, -160.917)
  line L9773 (67.1214, -214.923) -> (66.643, -214.587)
  line L9774 (74.4039, -216.096) -> (73.8346, -216.228)
  line L9775 (137.682, -198.309) -> (138.266, -198.302)
  line L9776 (78.1207, -200.614) -> (78.5428, -201.018)
  line L9777 (63.2379, -209.293) -> (63.1309, -208.719)
  line L9778 (67.6204, -215.227) -> (67.1214, -214.923)
  line L9779 (174.627, -165.089) -> (174.311, -164.598)
  line L9780 (175.084, -154.206) -> (175.469, -153.766)
  line L9781 (72.6391, -216.287) -> (73.2302, -216.23)
  line L9782 (76.954, -199.84) -> (76.4456, -199.533)
  line L9783 (145.544, -212.463) -> (145.199, -212.934)
  line L9784 (190.827, -157.638) -> (190.957, -158.208)
  line L9785 (75.3734, -199.024) -> (74.8143, -198.824)
  line L9786 (68.9847, -198.946) -> (68.4345, -199.169)
  line L9787 (79.57, -212.253) -> (79.8785, -211.746)
  line L9788 (179.386, -151.309) -> (179.949, -151.154)
  line L9789 (190.218, -155.997) -> (190.456, -156.531)
  line L9790 (69.9488, -198.554) -> (70.5208, -198.435)
  line L9791 (63.3803, -209.486) -> (63.541, -210.058)
  line L9792 (189.858, -164.57) -> (189.544, -165.063)
  line L9793 (143.673, -200.238) -> (144.121, -200.614)
  line L9794 (78.9379, -201.449) -> (79.3045, -201.904)
  line L9795 (143.203, -199.892) -> (143.673, -200.238)
  line L9796 (79.8006, -202.818) -> (79.4833, -202.317)
  line L9797 (181.099, -150.953) -> (181.682, -150.909)
  line L9798 (88.8893, -152.651) -> (88.417, -153.01)
  line L9799 (76.5813, -215.09) -> (77.0844, -214.774)
  line L9800 (64.3113, -211.998) -> (64.0276, -211.487)
  line L9801 (80.3914, -210.676) -> (80.5935, -210.117)
  line L9802 (73.2581, -216.323) -> (72.6766, -216.38)
  line L9803 (173.174, -160.917) -> (173.258, -161.505)
  line L9804 (66.8893, -200.051) -> (66.417, -200.41)
  line L9805 (174.975, -165.559) -> (174.627, -165.089)
  line L9806 (191.027, -161.288) -> (190.922, -161.862)
  line L9807 (87.5489, -153.82) -> (87.157, -154.266)
  line L9808 (85.1587, -159.138) -> (85.1245, -159.731)
  line L9809 (63.1297, -207.725) -> (63.1742, -208.317)
  line L9810 (191.127, -159.95) -> (191.125, -160.124)
  line L9811 (74.5713, -198.651) -> (75.1275, -198.83)
  line L9812 (186.199, -151.894) -> (186.711, -152.176)
  line L9813 (79.1334, -201.837) -> (78.7525, -201.381)
  line L9814 (183.43, -151.002) -> (184.005, -151.108)
  line L9815 (178.834, -151.501) -> (179.386, -151.309)
  line L9816 (68.0392, -215.343) -> (68.5778, -215.593)
  line L9817 (140.571, -198.651) -> (141.128, -198.83)
  line L9818 (146.389, -210.93) -> (146.14, -211.459)
  line L9819 (63.0291, -207.555) -> (63.0332, -207.131)
  line L9820 (76.0585, -215.371) -> (76.5813, -215.09)
  line L9821 (75.671, -199.044) -> (76.1995, -199.294)
  line L9822 (77.4411, -200.179) -> (76.954, -199.84)
  line L9823 (80.5935, -210.117) -> (80.7582, -209.547)
  line L9824 (131.469, -201.166) -> (131.882, -200.753)
  line L9825 (86.17, -155.746) -> (85.9088, -156.279)
  line L9826 (65.4688, -201.166) -> (65.8816, -200.753)
  line L9827 (66.1873, -214.221) -> (65.7561, -213.827)
  line L9828 (79.9457, -202.88) -> (80.2178, -203.397)
  line L9829 (64.1085, -203.06) -> (64.402, -202.554)
  line L9830 (80.2178, -203.397) -> (80.4559, -203.931)
  line L9831 (178.295, -151.728) -> (178.834, -151.501)
  line L9832 (129.622, -204.122) -> (129.848, -203.583)
  line L9833 (63.1742, -208.317) -> (63.2578, -208.905)
  line L9834 (80.9575, -205.608) -> (81.0514, -206.184)
  line L9835 (74.3945, -216) -> (74.9627, -215.827)
  line L9836 (70.9269, -216.327) -> (70.35, -216.234)
  line L9837 (175.351, -166.006) -> (174.975, -165.559)
  line L9838 (76.0441, -215.484) -> (75.5109, -215.723)
  line L9839 (79.4833, -202.317) -> (79.1334, -201.837)
  line L9840 (74.8143, -198.824) -> (74.2432, -198.661)
  line L9841 (129.277, -205.237) -> (129.432, -204.674)
  line L9842 (80.6591, -204.478) -> (80.8266, -205.038)
  line L9843 (80.3321, -203.88) -> (80.084, -203.34)
  line L9844 (179.949, -151.154) -> (180.521, -151.035)
  line L9845 (191.051, -158.784) -> (191.108, -159.366)
  line L9846 (189.304, -154.504) -> (189.641, -154.981)
  line L9847 (68.2951, -199.128) -> (68.8336, -198.901)
  line L9848 (145.641, -202.381) -> (145.946, -202.88)
  line L9849 (63.1245, -207.131) -> (63.1297, -207.725)
  line L9850 (63.4315, -204.674) -> (63.6222, -204.122)
  line L9851 (63.5618, -210.416) -> (63.3817, -209.86)
  line L9852 (72.0455, -216.305) -> (72.6391, -216.287)
  line L9853 (173.382, -162.46) -> (173.238, -161.893)
  line L9854 (176.643, -167.187) -> (176.187, -166.821)
  line L9855 (70.35, -216.234) -> (69.7803, -216.104)
  line L9856 (182.266, -150.902) -> (182.85, -150.933)
  line L9857 (189.641, -154.981) -> (189.946, -155.48)
  line L9858 (92.7068, -151.1) -> (92.1233, -151.211)
  line L9859 (146.827, -205.038) -> (146.957, -205.608)
  line L9860 (71.8893, -198.397) -> (71.2963, -198.429)
  line L9861 (173.432, -157.274) -> (173.622, -156.722)
  line L9862 (65.0836, -201.606) -> (65.4688, -201.166)
  line L9863 (80.084, -203.34) -> (79.8006, -202.818)
  line L9864 (184.571, -151.251) -> (185.128, -151.43)
  line L9865 (81.0211, -207.787) -> (81.0318, -207.35)
  line L9866 (147.125, -207.524) -> (147.095, -208.107)
  line L9867 (64.2446, -211.691) -> (64.5495, -212.201)
  line L9868 (71.5085, -216.382) -> (70.9269, -216.327)
  line L9869 (70.2761, -216.122) -> (70.8615, -216.222)
  line L9870 (65.8816, -200.753) -> (66.3203, -200.367)
  line L9871 (132.783, -200.01) -> (133.268, -199.684)
  line L9872 (87.9695, -153.401) -> (87.5489, -153.82)
  line L9873 (173.131, -161.319) -> (173.061, -160.739)
  line L9874 (80.1527, -211.219) -> (80.3914, -210.676)
  line L9875 (147.051, -206.184) -> (147.108, -206.766)
  line L9876 (143.99, -214.201) -> (143.536, -214.568)
  line L9877 (190.781, -162.429) -> (190.602, -162.986)
  line L9878 (64.8876, -212.689) -> (65.2572, -213.154)
  line L9879 (80.7806, -209.829) -> (80.6024, -210.386)
  line L9880 (81.0951, -208.107) -> (81.0274, -208.688)
  line L9881 (80.7185, -205.002) -> (80.5439, -204.435)
  line L9882 (180.927, -168.927) -> (180.35, -168.834)
  line L9883 (134.295, -199.128) -> (134.834, -198.901)
  line L9884 (129.432, -204.674) -> (129.622, -204.122)
  line L9885 (129.848, -203.583) -> (130.108, -203.06)
  line L9886 (73.2302, -216.23) -> (73.8162, -216.134)
  line L9887 (72.8498, -198.333) -> (73.4301, -198.402)
  line L9888 (65.6569, -213.593) -> (66.0847, -214.005)
  line L9889 (184.963, -168.527) -> (184.404, -168.696)
  line L9890 (186.044, -168.084) -> (185.511, -168.323)
  line L9891 (63.7774, -210.959) -> (63.5618, -210.416)
  line L9892 (88.417, -153.01) -> (87.9695, -153.401)
  line L9893 (178.672, -168.335) -> (178.138, -168.098)
  line L9894 (85.9088, -156.279) -> (85.6834, -156.829)
  line L9895 (68.4345, -199.169) -> (67.9003, -199.429)
  line L9896 (174.402, -155.154) -> (174.727, -154.669)
  line L9897 (183.258, -168.923) -> (182.677, -168.98)
  line L9898 (63.6222, -204.122) -> (63.8482, -203.583)
  line L9899 (137.099, -198.353) -> (137.682, -198.309)
  line L9900 (147.095, -208.107) -> (147.027, -208.688)
  line L9901 (66.0847, -214.005) -> (66.539, -214.387)
  line L9902 (67.0175, -214.739) -> (67.5183, -215.058)
  line L9903 (186.711, -152.176) -> (187.203, -152.492)
  line L9904 (76.5607, -215.211) -> (76.0441, -215.484)
  line L9905 (68.672, -215.735) -> (68.138, -215.498)
  line L9906 (68.138, -215.498) -> (67.6204, -215.227)
  line L9907 (66.417, -200.41) -> (65.9695, -200.801)
  line L9908 (129.078, -206.388) -> (129.159, -205.81)